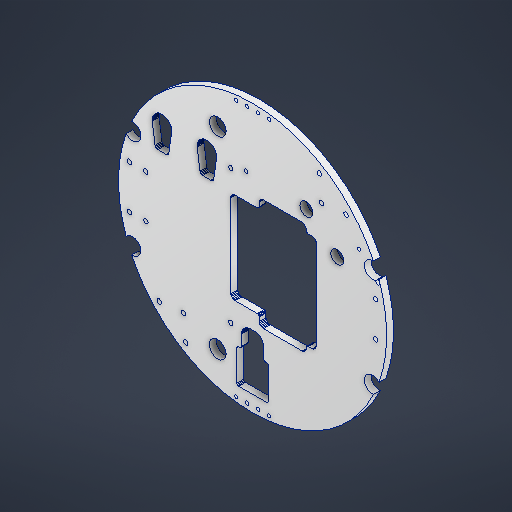
# Autodesk Inventor part: macro_mfd1004
Saved by Autodesk Inventor 2026.4 (Build 304435000, 435)
## iProperties
Created: 2026-11-03
Part Number: macro_mfd1004
Material: Alumínio 6061
Document SubType Name: Modeling
Designer: User
Density: 2.7 g/cm^3
Appearance: Alumínio - Plano
Author: User
Autodesk Inventor part; units mm, degrees
ref_plane "YZ Plane" through (0, 0, 0) normal (1, 0, 0) x (0, 1, 0)
ref_plane "XZ Plane" through (0, 0, 0) normal (0, 1, 0) x (-1, 0, 0)
sketch "Sketch_Base_Disk" plane through (0, 0, 0) normal (0, 0, 1) x (1, 0, 0)
  circle A0 centre (0, 0) radius 195.5038
  dimension "d42" = 391.0076
  constraints: 1 centre point
  measures "d42" diameter of A0
extrude "Base_Disk" add sketch "Sketch_Base_Disk" along normal blind 10.0076
ref_plane "Datum_A_Front_Face" through (0, 0, 10.0076) normal (0, 0, 1) x (1, 0, 0)
sketch "Sketch_Flats_Notches" plane through (0, 0, 0) normal (0, 0, 1) x (1, 0, 0)
  line L0 (0, 195.5038) -> (0, -195.5038)
  line L1 (195.5038, 0) -> (-195.5038, 0)
  line L2 (-270.4451, 112.022) -> (270.4451, -112.022)
  line L3 (297.3467, 123.165) -> (-297.3467, -123.165)
  circle A0 centre (0, 0) radius 195.5038 projected
  line L4 (180.622, -74.8161) -> (174.99, -72.4832)
  circle A1 centre (174.99, -72.4832) radius 12.0015
  circle A2 centre (0, 0) radius 189.4078
  circle A3 centre (-174.99, -72.4832) radius 12.0015
  circle A4 centre (-174.99, 72.4832) radius 12.0015
  circle A5 centre (174.99, 72.4832) radius 12.0015
  dimension "d21" = 67.5
  dimension "d22" = 67.5
  dimension "d23" = 6.096
  dimension "d24" = 24.003
  dimension "d25" = 24.003
  dimension "d26" = 24.003
  dimension "d27" = 24.003
  constraints: 10 end point, 5 centre point, 5 point on circle, 5 point on line, 4 midpoint, 2 coincident, 1 vertical
  measures "d21" angle of L0 L2
  measures "d22" angle of L0 L3
  measures "d23" distance of L4.start L4.end
  measures "d24" diameter of A1
  measures "d25" diameter of A3
  measures "d26" diameter of A4
  measures "d27" diameter of A5
extrude "Flats_Notches_DetailA" cut sketch "Sketch_Flats_Notches" along normal through all both and the other way through all contours A5 L3 A0 | A0 L3 A2 A5 | A4 A2 L2 A0 | A0 L2 A4 | A2 L3 A5 | A4 L2 A2 | A0 A5 A2 L3 | L3 A5 A0 | A0 A4 L2 | L2 A2 A4 A0 | A4 A2 L2 | A1 A2 L2 | L2 A2 A1 | L3 A2 A5 | A3 A2 L3 | L3 A2 A3 | A3 A0 L3 A2 | A2 L2 A0 A1 | A1 A0 L2 A2 | A2 L3 A0 A3 | A3 L3 A0 | A0 L2 A1 | A1 L2 A0 | A0 L3 A3
sketch "Esboço12" plane through (0, 0, 0) normal (0, 0, 1) x (1, 0, 0)
  line L0 (-31.75, 60.325) -> (-31.5646, 61.8439)
  line L1 (-31.5646, 61.8439) -> (-31.0236, 63.2765)
  line L2 (-31.0236, 63.2765) -> (-30.1523, 64.5363)
  line L3 (-30.1523, 64.5363) -> (-29.0068, 65.5498)
  line L4 (-29.0068, 65.5498) -> (-27.653, 66.2635)
  line L5 (-27.653, 66.2635) -> (-26.1645, 66.6293)
  line L6 (-26.1645, 66.6293) -> (6.35, 66.675)
  line L7 (6.35, 66.675) -> (7.4371, 66.8655)
  line L8 (7.4371, 66.8655) -> (8.3896, 67.4167)
  line L9 (8.3896, 67.4167) -> (9.1008, 68.2625)
  line L10 (9.1008, 68.2625) -> (9.4767, 69.2988)
  line L11 (9.4767, 69.2988) -> (9.525, 75.0062)
  line L12 (9.525, 75.0062) -> (9.7104, 76.5251)
  line L13 (9.7104, 76.5251) -> (10.2514, 77.9577)
  line L14 (10.2514, 77.9577) -> (11.1227, 79.2175)
  line L15 (11.1227, 79.2175) -> (12.2682, 80.231)
  line L16 (12.2682, 80.231) -> (13.622, 80.9447)
  line L17 (13.622, 80.9447) -> (15.1105, 81.3105)
  line L18 (15.1105, 81.3105) -> (71.8337, 81.3562)
  line L19 (71.8337, 81.3562) -> (73.3527, 81.1708)
  line L20 (73.3527, 81.1708) -> (74.7852, 80.6298)
  line L21 (74.7852, 80.6298) -> (76.0451, 79.7585)
  line L22 (76.0451, 79.7585) -> (77.0585, 78.613)
  line L23 (77.0585, 78.613) -> (77.7723, 77.2592)
  line L24 (77.7723, 77.2592) -> (78.138, 75.7707)
  line L25 (78.138, 75.7707) -> (78.1812, 74.2163)
  line L26 (78.1812, 74.2163) -> (78.3717, 73.1291)
  line L27 (78.3717, 73.1291) -> (78.9229, 72.1766)
  line L28 (78.9229, 72.1766) -> (79.7687, 71.4654)
  line L29 (79.7687, 71.4654) -> (80.805, 71.0895)
  line L30 (80.805, 71.0895) -> (86.5124, 71.0438)
  line L31 (86.5124, 71.0438) -> (88.0313, 70.8584)
  line L32 (88.0313, 70.8584) -> (89.4639, 70.3174)
  line L33 (89.4639, 70.3174) -> (90.7237, 69.4461)
  line L34 (90.7237, 69.4461) -> (91.7372, 68.3006)
  line L35 (91.7372, 68.3006) -> (92.4509, 66.9468)
  line L36 (92.4509, 66.9468) -> (92.8167, 65.4583)
  line L37 (92.8167, 65.4583) -> (92.8624, -64.6938)
  line L38 (92.8624, -64.6938) -> (92.677, -66.2127)
  line L39 (92.677, -66.2127) -> (92.136, -67.6453)
  line L40 (92.136, -67.6453) -> (91.2647, -68.9051)
  line L41 (91.2647, -68.9051) -> (90.1192, -69.9186)
  line L42 (90.1192, -69.9186) -> (88.7654, -70.6323)
  line L43 (88.7654, -70.6323) -> (87.2769, -70.9981)
  line L44 (87.2769, -70.9981) -> (81.3562, -71.0413)
  line L45 (81.3562, -71.0413) -> (80.2691, -71.2318)
  line L46 (80.2691, -71.2318) -> (79.3166, -71.7829)
  line L47 (79.3166, -71.7829) -> (78.6054, -72.6288)
  line L48 (78.6054, -72.6288) -> (78.2295, -73.6651)
  line L49 (78.2295, -73.6651) -> (78.1837, -75.0062)
  line L50 (78.1837, -75.0062) -> (77.9983, -76.5251)
  line L51 (77.9983, -76.5251) -> (77.4573, -77.9577)
  line L52 (77.4573, -77.9577) -> (76.5861, -79.2175)
  line L53 (76.5861, -79.2175) -> (75.4405, -80.231)
  line L54 (75.4405, -80.231) -> (74.0867, -80.9447)
  line L55 (74.0867, -80.9447) -> (72.5983, -81.3105)
  line L56 (72.5983, -81.3105) -> (15.875, -81.3562)
  line L57 (15.875, -81.3562) -> (14.3561, -81.1708)
  line L58 (14.3561, -81.1708) -> (12.9235, -80.6298)
  line L59 (12.9235, -80.6298) -> (11.6637, -79.7585)
  line L60 (11.6637, -79.7585) -> (10.6502, -78.613)
  line L61 (10.6502, -78.613) -> (9.9365, -77.2592)
  line L62 (9.9365, -77.2592) -> (9.5707, -75.7707)
  line L63 (9.5707, -75.7707) -> (9.525, -69.85)
  line L64 (9.525, -69.85) -> (9.3345, -68.7629)
  line L65 (9.3345, -68.7629) -> (8.7833, -67.8104)
  line L66 (8.7833, -67.8104) -> (7.9375, -67.0992)
  line L67 (7.9375, -67.0992) -> (6.9012, -66.7233)
  line L68 (6.9012, -66.7233) -> (-25.4, -66.675)
  line L69 (-25.4, -66.675) -> (-26.9189, -66.4896)
  line L70 (-26.9189, -66.4896) -> (-28.3515, -65.9486)
  line L71 (-28.3515, -65.9486) -> (-29.6113, -65.0773)
  line L72 (-29.6113, -65.0773) -> (-30.6248, -63.9318)
  line L73 (-30.6248, -63.9318) -> (-31.3385, -62.578)
  line L74 (-31.3385, -62.578) -> (-31.7043, -61.0895)
  line L75 (-31.7043, -61.0895) -> (-31.75, 60.325)
  line L76 (-15.875, -103.886) -> (-15.8064, -102.5576)
  line L77 (-15.8064, -102.5576) -> (-15.5981, -101.2444)
  line L78 (-15.5981, -101.2444) -> (-15.2527, -99.9617)
  line L79 (-15.2527, -99.9617) -> (-14.7777, -98.7196)
  line L80 (-14.7777, -98.7196) -> (-14.1732, -97.536)
  line L81 (-14.1732, -97.536) -> (-13.4493, -96.4209)
  line L82 (-13.4493, -96.4209) -> (-12.6136, -95.3872)
  line L83 (-12.6136, -95.3872) -> (-11.6738, -94.4474)
  line L84 (-11.6738, -94.4474) -> (-10.6401, -93.6117)
  line L85 (-10.6401, -93.6117) -> (-9.525, -92.8878)
  line L86 (-9.525, -92.8878) -> (-8.3414, -92.2833)
  line L87 (-8.3414, -92.2833) -> (-7.0993, -91.8083)
  line L88 (-7.0993, -91.8083) -> (-5.8166, -91.4629)
  line L89 (-5.8166, -91.4629) -> (-4.5034, -91.2546)
  line L90 (-4.5034, -91.2546) -> (-3.175, -91.186)
  line L91 (-3.175, -91.186) -> (3.175, -91.186)
  line L92 (3.175, -91.186) -> (4.5034, -91.2546)
  line L93 (4.5034, -91.2546) -> (5.8166, -91.4629)
  line L94 (5.8166, -91.4629) -> (7.0993, -91.8083)
  line L95 (7.0993, -91.8083) -> (8.3414, -92.2833)
  line L96 (8.3414, -92.2833) -> (9.525, -92.8878)
  line L97 (9.525, -92.8878) -> (10.6401, -93.6117)
  line L98 (10.6401, -93.6117) -> (11.6738, -94.4474)
  line L99 (11.6738, -94.4474) -> (12.6136, -95.3872)
  line L100 (12.6136, -95.3872) -> (13.4493, -96.4209)
  line L101 (13.4493, -96.4209) -> (14.1732, -97.536)
  line L102 (14.1732, -97.536) -> (14.7777, -98.7196)
  line L103 (14.7777, -98.7196) -> (15.2527, -99.9617)
  line L104 (15.2527, -99.9617) -> (15.5981, -101.2444)
  line L105 (15.5981, -101.2444) -> (15.8064, -102.5576)
  line L106 (15.8064, -102.5576) -> (15.875, -103.886)
  line L107 (15.875, -103.886) -> (15.875, -118.999)
  line L108 (15.875, -118.999) -> (16.0655, -120.0861)
  line L109 (16.0655, -120.0861) -> (16.6167, -121.0386)
  line L110 (16.6167, -121.0386) -> (17.4625, -121.7498)
  line L111 (17.4625, -121.7498) -> (18.4988, -122.1257)
  line L112 (18.4988, -122.1257) -> (20.193, -122.174)
  line L113 (20.193, -122.174) -> (21.2801, -122.3645)
  line L114 (21.2801, -122.3645) -> (22.2326, -122.9157)
  line L115 (22.2326, -122.9157) -> (22.9438, -123.7615)
  line L116 (22.9438, -123.7615) -> (23.3197, -124.7978)
  line L117 (23.3197, -124.7978) -> (23.368, -169.037)
  line L118 (23.368, -169.037) -> (23.081, -170.3553)
  line L119 (23.081, -170.3553) -> (22.2733, -171.4373)
  line L120 (22.2733, -171.4373) -> (21.0871, -172.0825)
  line L121 (21.0871, -172.0825) -> (-20.193, -172.212)
  line L122 (-20.193, -172.212) -> (-21.5113, -171.925)
  line L123 (-21.5113, -171.925) -> (-22.5933, -171.1173)
  line L124 (-22.5933, -171.1173) -> (-23.2385, -169.9311)
  line L125 (-23.2385, -169.9311) -> (-23.368, -125.349)
  line L126 (-23.368, -125.349) -> (-23.1775, -124.2619)
  line L127 (-23.1775, -124.2619) -> (-22.6263, -123.3094)
  line L128 (-22.6263, -123.3094) -> (-21.7805, -122.5982)
  line L129 (-21.7805, -122.5982) -> (-20.7442, -122.2223)
  line L130 (-20.7442, -122.2223) -> (-19.05, -122.174)
  line L131 (-19.05, -122.174) -> (-17.9629, -121.9835)
  line L132 (-17.9629, -121.9835) -> (-17.0104, -121.4323)
  line L133 (-17.0104, -121.4323) -> (-16.2992, -120.5865)
  line L134 (-16.2992, -120.5865) -> (-15.9233, -119.5502)
  line L135 (-15.9233, -119.5502) -> (-15.875, -103.886)
  line L136 (-138.2192, 67.818) -> (-139.6086, 68.0618)
  line L137 (-139.6086, 68.0618) -> (-140.8303, 68.768)
  line L138 (-140.8303, 68.768) -> (-141.7396, 69.85)
  line L139 (-141.7396, 69.85) -> (-142.2222, 71.1759)
  line L140 (-142.2222, 71.1759) -> (-146.3573, 99.7052)
  line L141 (-146.3573, 99.7052) -> (-146.4259, 101.0996)
  line L142 (-146.4259, 101.0996) -> (-146.3573, 102.4941)
  line L143 (-146.3573, 102.4941) -> (-146.1516, 103.8758)
  line L144 (-146.1516, 103.8758) -> (-145.8138, 105.2297)
  line L145 (-145.8138, 105.2297) -> (-145.3439, 106.5428)
  line L146 (-145.3439, 106.5428) -> (-144.747, 107.8052)
  line L147 (-144.747, 107.8052) -> (-144.0282, 109.0016)
  line L148 (-144.0282, 109.0016) -> (-143.1976, 110.1242)
  line L149 (-143.1976, 110.1242) -> (-142.2603, 111.158)
  line L150 (-142.2603, 111.158) -> (-141.2265, 112.0953)
  line L151 (-141.2265, 112.0953) -> (-140.1039, 112.9259)
  line L152 (-140.1039, 112.9259) -> (-138.9075, 113.6447)
  line L153 (-138.9075, 113.6447) -> (-137.6451, 114.2416)
  line L154 (-137.6451, 114.2416) -> (-136.332, 114.7115)
  line L155 (-136.332, 114.7115) -> (-134.9781, 115.0493)
  line L156 (-134.9781, 115.0493) -> (-133.5964, 115.255)
  line L157 (-133.5964, 115.255) -> (-132.2019, 115.3236)
  line L158 (-132.2019, 115.3236) -> (-130.8075, 115.255)
  line L159 (-130.8075, 115.255) -> (-129.4257, 115.0493)
  line L160 (-129.4257, 115.0493) -> (-128.0719, 114.7115)
  line L161 (-128.0719, 114.7115) -> (-126.7587, 114.2416)
  line L162 (-126.7587, 114.2416) -> (-125.4963, 113.6447)
  line L163 (-125.4963, 113.6447) -> (-124.3, 112.9259)
  line L164 (-124.3, 112.9259) -> (-123.1773, 112.0953)
  line L165 (-123.1773, 112.0953) -> (-122.1435, 111.158)
  line L166 (-122.1435, 111.158) -> (-121.2063, 110.1242)
  line L167 (-121.2063, 110.1242) -> (-120.3757, 109.0016)
  line L168 (-120.3757, 109.0016) -> (-119.6569, 107.8052)
  line L169 (-119.6569, 107.8052) -> (-119.06, 106.5428)
  line L170 (-119.06, 106.5428) -> (-118.5901, 105.2297)
  line L171 (-118.5901, 105.2297) -> (-118.2522, 103.8758)
  line L172 (-118.2522, 103.8758) -> (-118.0465, 102.4941)
  line L173 (-118.0465, 102.4941) -> (-117.9779, 101.0996)
  line L174 (-117.9779, 101.0996) -> (-118.0465, 99.7052)
  line L175 (-118.0465, 99.7052) -> (-122.1969, 71.1759)
  line L176 (-122.1969, 71.1759) -> (-122.6795, 69.85)
  line L177 (-122.6795, 69.85) -> (-123.5888, 68.768)
  line L178 (-123.5888, 68.768) -> (-124.8105, 68.0618)
  line L179 (-124.8105, 68.0618) -> (-126.1999, 67.818)
  line L180 (-126.1999, 67.818) -> (-138.2192, 67.818)
  line L181 (-72.6923, 67.818) -> (-74.0816, 68.0618)
  line L182 (-74.0816, 68.0618) -> (-75.3034, 68.768)
  line L183 (-75.3034, 68.768) -> (-76.2127, 69.85)
  line L184 (-76.2127, 69.85) -> (-76.6953, 71.1759)
  line L185 (-76.6953, 71.1759) -> (-80.8253, 99.7026)
  line L186 (-80.8253, 99.7026) -> (-80.8939, 101.0971)
  line L187 (-80.8939, 101.0971) -> (-80.8253, 102.4915)
  line L188 (-80.8253, 102.4915) -> (-80.6196, 103.8733)
  line L189 (-80.6196, 103.8733) -> (-80.2818, 105.2271)
  line L190 (-80.2818, 105.2271) -> (-79.8119, 106.5403)
  line L191 (-79.8119, 106.5403) -> (-79.215, 107.8027)
  line L192 (-79.215, 107.8027) -> (-78.4962, 108.999)
  line L193 (-78.4962, 108.999) -> (-77.6656, 110.1217)
  line L194 (-77.6656, 110.1217) -> (-76.7283, 111.1555)
  line L195 (-76.7283, 111.1555) -> (-75.6945, 112.0927)
  line L196 (-75.6945, 112.0927) -> (-74.5719, 112.9233)
  line L197 (-74.5719, 112.9233) -> (-73.3755, 113.6421)
  line L198 (-73.3755, 113.6421) -> (-72.1131, 114.239)
  line L199 (-72.1131, 114.239) -> (-70.8, 114.7089)
  line L200 (-70.8, 114.7089) -> (-69.4461, 115.0468)
  line L201 (-69.4461, 115.0468) -> (-68.0644, 115.2525)
  line L202 (-68.0644, 115.2525) -> (-66.6699, 115.3211)
  line L203 (-66.6699, 115.3211) -> (-65.2755, 115.2525)
  line L204 (-65.2755, 115.2525) -> (-63.8937, 115.0468)
  line L205 (-63.8937, 115.0468) -> (-62.5399, 114.7089)
  line L206 (-62.5399, 114.7089) -> (-61.2267, 114.239)
  line L207 (-61.2267, 114.239) -> (-59.9643, 113.6421)
  line L208 (-59.9643, 113.6421) -> (-58.768, 112.9233)
  line L209 (-58.768, 112.9233) -> (-57.6453, 112.0927)
  line L210 (-57.6453, 112.0927) -> (-56.6115, 111.1555)
  line L211 (-56.6115, 111.1555) -> (-55.6743, 110.1217)
  line L212 (-55.6743, 110.1217) -> (-54.8437, 108.999)
  line L213 (-54.8437, 108.999) -> (-54.1249, 107.8027)
  line L214 (-54.1249, 107.8027) -> (-53.528, 106.5403)
  line L215 (-53.528, 106.5403) -> (-53.0581, 105.2271)
  line L216 (-53.0581, 105.2271) -> (-52.7202, 103.8733)
  line L217 (-52.7202, 103.8733) -> (-52.5145, 102.4915)
  line L218 (-52.5145, 102.4915) -> (-52.4459, 101.0971)
  line L219 (-52.4459, 101.0971) -> (-52.5145, 99.7026)
  line L220 (-52.5145, 99.7026) -> (-56.6623, 71.1759)
  line L221 (-56.6623, 71.1759) -> (-57.1449, 69.85)
  line L222 (-57.1449, 69.85) -> (-58.0542, 68.768)
  line L223 (-58.0542, 68.768) -> (-59.276, 68.0618)
  line L224 (-59.276, 68.0618) -> (-60.6654, 67.818)
  line L225 (-60.6654, 67.818) -> (-72.6923, 67.818)
  constraints: 452 end point
extrude "Windows_and_Cutouts" cut sketch "Esboço12" along normal through all both and the other way through all
sketch "Esboço13" plane through (0, 0, 0) normal (0, 0, 1) x (1, 0, 0)
  circle A0 centre (-50.8, 140.716) radius 12.319
  circle A1 centre (-50.8, -140.716) radius 12.319
  circle A2 centre (78.4682, 100.9421) radius 9.525
  circle A3 centre (123.4745, 63.1723) radius 9.525
  circle A4 centre (-24.003, 187.325) radius 2.4892
  circle A5 centre (-8.001, 187.325) radius 2.4892
  circle A6 centre (8.001, 187.325) radius 2.4892
  circle A7 centre (24.003, 187.325) radius 2.4892
  circle A8 centre (-24.003, -187.325) radius 2.4892
  circle A9 centre (-8.001, -187.325) radius 2.4892
  circle A10 centre (8.001, -187.325) radius 2.4892
  circle A11 centre (24.003, -187.325) radius 2.4892
  circle A12 centre (97.3836, 155.5648) radius 3.2639
  circle A13 centre (100.5129, 119.7813) radius 3.2639
  circle A14 centre (136.2964, 122.9055) radius 3.2639
  circle A15 centre (-97.3836, -155.5623) radius 3.2639
  circle A16 centre (-100.5129, -119.7762) radius 3.2639
  circle A17 centre (-136.2964, -122.9055) radius 3.2639
  circle A18 centre (-179.5018, 31.7576) radius 3.2639
  circle A19 centre (-155.702, 31.3487) radius 3.2639
  circle A20 centre (-179.5018, -31.7424) radius 3.2639
  circle A21 centre (-155.702, -31.3334) radius 3.2639
  circle A22 centre (179.6237, 37.7952) radius 3.2639
  circle A23 centre (179.6263, -12.9972) radius 3.2639
  circle A24 centre (-31.7449, 97.7951) radius 3.2639
  circle A25 centre (-31.7551, -97.7824) radius 3.2639
  circle A26 centre (155.0213, 88.7755) radius 2.4765
  circle A27 centre (182.6387, 60.3961) radius 3.048
  circle A28 centre (-9.5326, 104.7725) radius 2.794
  constraints: 29 centre point
extrude "Assembly_Mounting_Holes" cut sketch "Esboço13" along normal through all both and the other way through all
